testingThreadstat (Autodesk Fusion 360 design; units mm, degrees)
Autodesk Fusion 360 part; units mm, degrees
sketch "Sketch1" plane through (0, 0, 0) normal (0, 1, 0) x (1, 0, 0)
  circle A0 centre (0, 0) radius 8
  circle A1 centre (0, 0) radius 15
  dimension "d1" = 16
  dimension "d2" = 30
  constraint coincident A0.centre A1.centre
  constraint concentric A0 A1
  measures "d1" diameter of A0
  measures "d2" diameter of A1
extrude "Extrude1" add sketch "Sketch1" along normal blind 20
thread "Thread1" "ISO Metric profile 16.0 M16x2 6H" major diameter 16.2505 minor diameter 14.0225 pitch 2 angle 60 modelled right hand crest width 0.5471 on face at (7.9901, 13.3333, 0.3988) crest through (7.0113, 0.5, 0)
sketch "Sketch2" plane through (0, 0, 0) normal (0, -1, 0) x (1, 0, 0)
  spline S0 degree 3 poles (-2.1021, -7.8486) (-3.0882, -7.5115) (-3.9999, -6.9874) (-5.547, -5.6335) (-6.1742, -4.8248) (-7.0665, -3.0348) (-7.3323, -2.0756) (-7.474, -0.1364) (-7.359, 0.8239) (-6.8842, 2.2736) (-6.6448, 2.7903) (-6.0538, 3.7474) (-5.7062, 4.1857) (-5.3104, 4.5779) knots 0 0 0 0 0.312647 0.312647 0.617102 0.617102 0.913361 0.913361 1.201422 1.201422 1.372094 1.372094 1.539736 1.539736 1.539736 1.539736
  arc A0 (5.3104, 4.5779) -> (-5.3104, 4.5779) centre (0, 0) ccw
  spline S1 degree 3 poles (5.3104, 4.5779) (5.9665, 3.9278) (6.4873, 3.1541) (7.2188, 1.4267) (7.4128, 0.4857) (7.4345, -1.4459) (7.2515, -2.4177) (6.5178, -4.2648) (5.9644, -5.1181) (4.8302, -6.2937) (4.3436, -6.6903) (3.2791, -7.3671) (2.7037, -7.6429) (2.1021, -7.8486) knots 0 0 0 0 0.277113 0.277113 0.562406 0.562406 0.855875 0.855875 1.157518 1.157518 1.344724 1.344724 1.53496 1.53496 1.53496 1.53496
  arc A1 (-2.1021, -7.8486) -> (2.1021, -7.8486) centre (0, 0) ccw
  circle A2 centre (0, 0) radius 15
  line L0 (8, 1.5) -> (-8, 1.5)
  line L1 (-8, 1.5) -> (-8, -1.5)
  line L2 (-8, -1.5) -> (8, -1.5)
  line L3 (8, -1.5) -> (8, 1.5)
  line L4 (8, 1.5) -> (-8, -1.5) construction
  line L5 (-8, 1.5) -> (8, -1.5) construction
  dimension "d5" = 16
  dimension "d6" = 3
  constraint perpendicular L0 L1
  constraint parallel L0 L2
  constraint parallel L1 L3
  constraint horizontal L0
  constraint coincident L4 A0.centre
  constraint coincident L5 A0.centre
  constraint coincident A0.centre A1.centre
  measures "d5" distance of L1.end L2.end
  measures "d6" distance of L0.end L1.end
extrude "Extrude2" cut sketch "Sketch2" against normal blind 14.5 contours S0 L0 L1 L2 | S0 S1 L0 L2 | S1 L0 L2 L3
